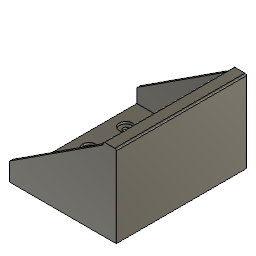
solderStation (Autodesk Fusion 360 design; units mm, degrees)
part number: 2026-08-10-19-56-16-923
Autodesk Fusion 360 part; units mm, degrees
sketch "Sketch1" plane through (0, 0, 0) normal (0, 0, 1) x (1, 0, 0)
  line L0 (-28, 37) -> (62, 37)
  line L1 (62, 37) -> (62, 18)
  line L2 (62, 18) -> (-28, 18)
  line L3 (-28, 18) -> (-28, 37)
  dimension "d1" = 90
  dimension "d2" = 19
  constraint horizontal L0
  constraint vertical L1
  constraint horizontal L2
  constraint vertical L3
  measures "d1" distance of L0.start L0.end
  measures "d2" distance of L0.start L2.end
extrude "Extrude1" add sketch "Sketch1" along normal blind 6 makes body 1
sketch "Sketch2" plane through (0, 0, 6) normal (0, 0, 1) x (-1, 0, 0)
  line L0 (28, -37) -> (28, -18)
  line L1 (28, -18) -> (-62, -18)
  line L2 (-62, -18) -> (-62, -37)
  line L3 (-62, -37) -> (28, -37)
ref_plane "WorkPlane1" through (17, 27.5, 6) normal (0, 0, 1) x (-1, 0, 0)
sketch "Sketch3" plane through (0, 0, 6) normal (0, 0, 1) x (1, 0, 0)
  line L0 (17, 37) -> (17, 18)
  circle A0 centre (-8, 27.5) radius 8.9
  circle A1 centre (42, 27.5) radius 8.9
  circle A2 centre (-8, 27.5) radius 3.65
  circle A3 centre (42, 27.5) radius 3.65
  dimension "d13" = 17.8
  dimension "d14" = 17.8
  dimension "d15" = 7.3
  dimension "d16" = 7.3
  constraint vertical L0
  constraint concentric A0 A2
  constraint concentric A1 A3
  measures "d13" diameter of A0
  measures "d14" diameter of A1
  measures "d15" diameter of A2
  measures "d16" diameter of A3
extrude "Extrude2" cut sketch "Sketch3" against normal blind 7 contours A2 | A3 bodies 1
extrude "Extrude3" cut sketch "Sketch3" against normal blind 3 bodies 1
sketch "Sketch4" plane through (0, 0, 0) normal (0, 0, 1) x (1, 0, 0)
  line L0 (-21, 37) -> (55, 37)
  line L1 (55, 37) -> (55, 39)
  line L2 (55, 39) -> (-21, 39)
  line L3 (-21, 39) -> (-21, 37)
  dimension "d21" = 76
  dimension "d22" = 2
  constraint horizontal L0
  constraint vertical L1
  constraint horizontal L2
  constraint vertical L3
  measures "d21" distance of L0.start L0.end
  measures "d22" distance of L0.start L2.end
copy_body "CopyPasteBodies1" bodies 1 makes body 2
move_body "Move1" bodies 2 to x (1, 0, 0) y (0, 1, 0) z (0, 0, 1) at (-50, 0, 0)
copy_body "CopyPasteBodies2" bodies 1 2 makes body 3 makes body 4
move_body "Move2" bodies 3 4 to x (1, 0, 0) y (0, 1, 0) z (0, 0, 1) at (0, 50, 0)
copy_body "CopyPasteBodies3" bodies 3 4 makes body 5 makes body 6
move_body "Move3" bodies 5 6 to x (1, 0, 0) y (0, 1, 0) z (0, 0, 1) at (0, 50, 0)
sketch "Sketch7" plane through (0, 0, 6) normal (0, 0, 1) x (-1, 0, 0)
  circle A0 centre (8, -27.5) radius 8.9
  circle A1 centre (58, -27.5) radius 8.9
  line L0 (78, -18) -> (-12, -18)
  line L1 (-12, -18) -> (-12, -37)
  line L2 (-12, -37) -> (78, -37)
  line L3 (78, -37) -> (78, -18)
  line L4 (78, -37) -> (-62, -37)
  line L5 (-62, -37) -> (-62, -68)
  line L6 (-62, -68) -> (78, -68)
  line L7 (78, -68) -> (78, -37)
  constraint horizontal L4
  constraint vertical L5
  constraint horizontal L6
  constraint vertical L7
  constraint coincident L2.end L3.start
extrude "Extrude7" add sketch "Sketch7" against normal blind 6 contours L2 L4 L5 L6 L7 bodies 1 2 3 4
sketch "Sketch8" plane through (0, 0, 6) normal (0, 0, 1) x (-1, 0, 0)
  circle A0 centre (-42, -27.5) radius 8.9
  circle A1 centre (8, -27.5) radius 8.9
  circle A2 centre (58, -27.5) radius 8.9
  circle A3 centre (58, -77.5) radius 8.9
  circle A4 centre (8, -77.5) radius 8.9
  line L0 (-62, -68) -> (-62, -87)
  line L1 (-62, -87) -> (78, -87)
  line L2 (78, -87) -> (78, -68)
  line L3 (78, -68) -> (78, -18)
  line L4 (78, -18) -> (-62, -18)
  line L5 (-62, -18) -> (-62, -37)
  line L6 (-62, -37) -> (-62, -68)
  circle A5 centre (-42, -77.5) radius 8.9
  line L7 (78, -87) -> (-62, -87)
  line L8 (-62, -87) -> (-62, -118)
  line L9 (-62, -118) -> (78, -118)
  line L10 (78, -118) -> (78, -87)
  constraint horizontal L7
  constraint vertical L8
  constraint horizontal L9
  constraint vertical L10
  constraint coincident L1.end L2.start
extrude "Extrude8" add sketch "Sketch8" against normal blind 6 contours L1 L7 L8 L9 L10 bodies 1 5 6
sketch "Sketch9" plane through (0, 0, 6) normal (0, 0, 1) x (-1, 0, 0)
  circle A0 centre (-42, -77.5) radius 8.9
  circle A1 centre (8, -77.5) radius 8.9
  circle A2 centre (58, -77.5) radius 8.9
  circle A3 centre (58, -27.5) radius 8.9
  circle A4 centre (8, -27.5) radius 8.9
  circle A5 centre (-42, -27.5) radius 8.9
  circle A6 centre (58, -127.5) radius 8.9
  circle A7 centre (8, -127.5) radius 8.9
  line L0 (-62, -68) -> (-62, -137)
  line L1 (-62, -137) -> (78, -137)
  line L2 (78, -137) -> (78, -68)
  line L3 (78, -68) -> (78, -18)
  line L4 (78, -18) -> (-62, -18)
  line L5 (-62, -18) -> (-62, -37)
  line L6 (-62, -37) -> (-62, -68)
  circle A8 centre (-42, -127.5) radius 8.9
  line L7 (-62, -18) -> (78, -18)
  line L8 (78, -18) -> (78, 7.5)
  line L9 (78, 7.5) -> (-62, 7.5)
  line L10 (-62, 7.5) -> (-62, -18)
  dimension "d41" = 140
  dimension "d42" = 25.5
  constraint horizontal L7
  constraint vertical L8
  constraint horizontal L9
  constraint vertical L10
  constraint coincident L4.end L5.start
  measures "d41" distance of L4.end L3.end
  measures "d42" distance of L4.end L9.end
extrude "Extrude9" add sketch "Sketch9" against normal blind 6 contours L4 L7 L8 L9 L10 bodies 1
sketch "Sketch10" plane through (0, 0, 6) normal (0, 0, 1) x (-1, 0, 0)
  circle A0 centre (-42, -77.5) radius 8.9
  circle A1 centre (8, -77.5) radius 8.9
  circle A2 centre (58, -77.5) radius 8.9
  circle A3 centre (58, -27.5) radius 8.9
  circle A4 centre (8, -27.5) radius 8.9
  circle A5 centre (-42, -27.5) radius 8.9
  circle A6 centre (58, -127.5) radius 8.9
  circle A7 centre (8, -127.5) radius 8.9
  line L0 (-62, -68) -> (-62, -137)
  line L1 (-62, -137) -> (78, -137)
  line L2 (78, -137) -> (78, -68)
  line L3 (78, -68) -> (78, 7.5)
  line L4 (78, 7.5) -> (-62, 7.5)
  line L5 (-62, 7.5) -> (-62, -37)
  line L6 (-62, -37) -> (-62, -68)
  circle A8 centre (-42, -127.5) radius 8.9
  line L7 (-62, -137) -> (78, -137)
  line L8 (78, -137) -> (78, -162.5)
  line L9 (78, -162.5) -> (-62, -162.5)
  line L10 (-62, -162.5) -> (-62, -137)
  dimension "d45" = 140
  dimension "d46" = 25.5
  constraint horizontal L7
  constraint vertical L8
  constraint horizontal L9
  constraint vertical L10
  constraint coincident L0.end L1.start
  measures "d45" distance of L0.end L1.end
  measures "d46" distance of L0.end L9.end
extrude "Extrude10" add sketch "Sketch10" against normal blind 6 contours L1 L7 L8 L9 L10 bodies 1
sketch "Sketch11" plane through (0, 0, 6) normal (0, 0, 1) x (-1, 0, 0)
  circle A0 centre (-42, -77.5) radius 8.9
  circle A1 centre (8, -77.5) radius 8.9
  circle A2 centre (58, -77.5) radius 8.9
  circle A3 centre (58, -27.5) radius 8.9
  circle A4 centre (8, -27.5) radius 8.9
  circle A5 centre (-42, -27.5) radius 8.9
  circle A6 centre (58, -127.5) radius 8.9
  circle A7 centre (8, -127.5) radius 8.9
  line L0 (-62, -68) -> (-62, -162.5)
  line L1 (-62, -162.5) -> (78, -162.5)
  line L2 (78, -162.5) -> (78, -68)
  line L3 (78, -68) -> (78, 7.5)
  line L4 (78, 7.5) -> (-62, 7.5)
  line L5 (-62, 7.5) -> (-62, -37)
  line L6 (-62, -37) -> (-62, -68)
  circle A8 centre (-42, -127.5) radius 8.9
  line L7 (-62, 7.5) -> (-68, 7.5)
  line L8 (-68, 7.5) -> (-68, -162.5)
  line L9 (-68, -162.5) -> (-62, -162.5)
  line L10 (-62, -162.5) -> (-62, 7.5)
  dimension "d49" = 6
  constraint horizontal L7
  constraint vertical L8
  constraint horizontal L9
  constraint vertical L10
  constraint coincident L4.end L5.start
  measures "d49" distance of L4.end L7.end
extrude "Extrude11" add sketch "Sketch11" along normal blind 102 separate body contours L0 L5 L6 L7 L8 L9 L10 makes body 7
extrude "Extrude12" add 1 faces at (66, 74.3333, 6) along direction (0, 0, -1) blind 6 on bodies 7 bodies 1 7
sketch "Sketch12" plane through (0, -7.5, 0) normal (0, -1, 0) x (1, 0, 0)
  line L0 (62, 6) -> (-78, 6)
  line L1 (-78, 6) -> (-78, 0)
  line L2 (-78, 0) -> (68, 0)
  line L3 (68, 0) -> (68, 108)
  line L4 (68, 108) -> (62, 108)
  line L5 (62, 108) -> (62, 6)
  line L6 (62, 108) -> (50, 108)
  line L7 (-78, 6) -> (-78, 25)
  line L8 (-78, 25) -> (50, 108)
  constraint coincident L4.end L5.start
  constraint perpendicular L5 L6
  constraint coincident L0.end L1.start
  constraint perpendicular L0 L7
extrude "Extrude13" add sketch "Sketch12" along normal blind 4 separate body contours L0 L5 L6 L7 L8 makes body 8
extrude "Extrude14" add 1 faces at (17.3333, -7.5, 2) along direction (0, -1, 0) blind 4 on bodies 1 bodies 1 8
sketch "Sketch13" plane through (0, 162.5, 0) normal (0, 1, 0) x (-1, 0, 0)
  line L0 (78, 6) -> (-62, 6)
  line L1 (-62, 6) -> (-62, 108)
  line L2 (-62, 108) -> (-68, 108)
  line L3 (-68, 108) -> (-68, 0)
  line L4 (-68, 0) -> (78, 0)
  line L5 (78, 0) -> (78, 6)
  line L6 (-68, 108) -> (-50, 108)
  line L7 (-50, 108) -> (78, 25)
  line L8 (78, 25) -> (78, 0)
  constraint coincident L2.end L3.start
  constraint perpendicular L3 L6
  constraint coincident L4.end L5.start
extrude "Extrude15" add sketch "Sketch13" along normal blind 4 separate body contours L0 L1 L6 L7 L8 makes body 9
extrude "Extrude16" add 1 faces at (17.3333, 162.5, 2) along direction (0, 1, 0) blind 4 on bodies 1 bodies 1 9
sketch "Sketch14" plane through (0, 0, 108) normal (0, 0, 1) x (-1, 0, 0)
  line L0 (-62, -162.5) -> (-62, 7.5)
  line L1 (-62, 7.5) -> (-50, 7.5)
  line L2 (-50, 7.5) -> (-50, 11.5)
  line L3 (-50, 11.5) -> (-68, 11.5)
  line L4 (-68, 11.5) -> (-68, -166.5)
  line L5 (-68, -166.5) -> (-50, -166.5)
  line L6 (-50, -166.5) -> (-50, -162.5)
  line L7 (-50, -162.5) -> (-62, -162.5)
  line L8 (-68, 11.5) -> (-50, 11.5)
  line L9 (-50, 11.5) -> (-50, -166.5)
  line L10 (-50, -166.5) -> (-68, -166.5)
  line L11 (-68, -166.5) -> (-68, 11.5)
  constraint horizontal L8
  constraint vertical L9
  constraint horizontal L10
  constraint vertical L11
  constraint coincident L5.end L6.start
  constraint coincident L3.end L4.start
extrude "Extrude17" add sketch "Sketch14" along normal blind 4 bodies 1
fillet "Fillet3" radius 2 2 edges at (50, -9.5, 108) (50, 164.5, 108) on bodies 1
fillet "Fillet4" radius 2 1 edges at (68, 77.5, 112) on bodies 1
fillet "Fillet5" radius 2 2 edges at (-78, 164.5, 25) (-78, -9.5, 25) on bodies 1
fillet "Fillet6" radius 2 1 edges at (50, 77.5, 112) on bodies 1
